Autodesk Fusion 360 part; units mm, degrees
(part 4 of 5)
extrude "flange screw hole (1)" cut sketch "flange screw hole" along normal blind 26 bodies 30 in component "Gripper handle (printed)"
ref_plane "WorkPlane17" through (12.3, 0, 0) normal (1, 0, 0) x (0, 1, 0) in component "Gripper handle (printed)"
sketch "flange screw tunnel" plane through (12.3, 0, 0) normal (1, 0, 0) x (0, 0, -1) in component "Gripper handle (printed)"
  circle A0 centre (-5, 9.5) radius 3.2
extrude "flange screw tunnel (1)" cut sketch "flange screw tunnel" along normal blind 131.7 bodies 30 in component "Gripper handle (printed)"
sketch "flange screw hole (1)" plane through (7.3, 0, 0) normal (1, 0, 0) x (0, 0, -1) in component "Gripper handle (printed)"
  circle A0 centre (-8, 16.5) radius 1.7
extrude "flange screw hole (2)" cut sketch "flange screw hole (1)" along normal blind 26 bodies 30 in component "Gripper handle (printed)"
sketch "flange screw tunnel (1)" plane through (12.3, 0, 0) normal (1, 0, 0) x (0, 0, -1) in component "Gripper handle (printed)"
  circle A0 centre (-8, 16.5) radius 3.2
extrude "flange screw tunnel (2)" cut sketch "flange screw tunnel (1)" along normal blind 131.7 bodies 30 in component "Gripper handle (printed)"
ref_plane "WorkPlane18" through (0, 13, 0) normal (0, 1, 0) x (0, 0, 1) in component "Gripper handle (printed)"
sketch "rail insert hole (3)" plane through (0, 13, 0) normal (0, 1, 0) x (1, 0, 0) in component "Gripper handle (printed)"
  circle A0 centre (22.5, 0) radius 2
extrude "rail insert hole (1)'" cut sketch "rail insert hole (3)" along normal blind 8 bodies 30 in component "Gripper handle (printed)"
sketch "rail insert hole (1) (2)" plane through (0, 13, 0) normal (0, 1, 0) x (1, 0, 0) in component "Gripper handle (printed)"
  circle A0 centre (72.5, 0) radius 2
extrude "rail insert hole (2)'" cut sketch "rail insert hole (1) (2)" along normal blind 8 bodies 30 in component "Gripper handle (printed)"
sketch "rail insert hole (2) (2)" plane through (0, 13, 0) normal (0, 1, 0) x (1, 0, 0) in component "Gripper handle (printed)"
  circle A0 centre (122.5, 0) radius 2
extrude "rail insert hole (3)'" cut sketch "rail insert hole (2) (2)" along normal blind 8 bodies 30 in component "Gripper handle (printed)"
ref_plane "WorkPlane19" through (0, 18, 0) normal (0, 1, 0) x (0, 0, 1) in component "Gripper handle (printed)"
sketch "pusher insert hole" plane through (0, 18, 0) normal (0, 1, 0) x (1, 0, 0) in component "Gripper handle (printed)"
  circle A0 centre (122.5, -58) radius 2
extrude "pusher insert hole (1)" cut sketch "pusher insert hole" along normal blind 7 bodies 30 in component "Gripper handle (printed)"
ref_plane "WorkPlane1" through (0, 15.9, 0) normal (0, 1, 0) x (0, 0, 1) in component "Gripper HW fixed (buy)"
sketch "#4 x 3/8\" pan-head self-tapping screw, pipe (buy)" plane through (0, 15.9, 0) normal (0, 1, 0) x (1, 0, 0) in component "Gripper HW fixed (buy)"
  circle A0 centre (-124, 0) radius 2.8
extrude "#4 x 3/8\" pan-head self-tapping screw, pipe (buy) (1)" add sketch "#4 x 3/8\" pan-head self-tapping screw, pipe (buy)" against normal blind 2.4 separate body makes body 41 in component "Gripper HW fixed (buy)"
ref_plane "WorkPlane2" through (0, 13.5, 0) normal (0, 1, 0) x (0, 0, 1) in component "Gripper HW fixed (buy)"
sketch "#4 x 3/8\" pan-head self-tapping screw, pipe (buy) shank" plane through (0, 13.5, 0) normal (0, 1, 0) x (1, 0, 0) in component "Gripper HW fixed (buy)"
  circle A0 centre (-124, 0) radius 1.45
extrude "#4 x 3/8\" pan-head self-tapping screw, pipe (buy) shank (1)" add sketch "#4 x 3/8\" pan-head self-tapping screw, pipe (buy) shank" against normal blind 9.5 bodies 41 in component "Gripper HW fixed (buy)"
sketch "#4 x 3/8\" pan-head self-tapping screw, pipe (buy) (1)" plane through (0, 15.9, 0) normal (0, 1, 0) x (1, 0, 0) in component "Gripper HW fixed (buy)"
  circle A0 centre (-44, 0) radius 2.8
extrude "#4 x 3/8\" pan-head self-tapping screw, pipe (buy) (2)" add sketch "#4 x 3/8\" pan-head self-tapping screw, pipe (buy) (1)" against normal blind 2.4 separate body makes body 42 in component "Gripper HW fixed (buy)"
sketch "#4 x 3/8\" pan-head self-tapping screw, pipe (buy) shank (1)" plane through (0, 13.5, 0) normal (0, 1, 0) x (1, 0, 0) in component "Gripper HW fixed (buy)"
  circle A0 centre (-44, 0) radius 1.45
extrude "#4 x 3/8\" pan-head self-tapping screw, pipe (buy) shank (2)" add sketch "#4 x 3/8\" pan-head self-tapping screw, pipe (buy) shank (1)" against normal blind 9.5 bodies 42 in component "Gripper HW fixed (buy)"
ref_plane "WorkPlane3" through (5.4, 0, 0) normal (1, 0, 0) x (0, 1, 0) in component "Gripper HW fixed (buy)"
sketch "#4 x 3/8\" pan-head self-tapping screw, ring (buy)" plane through (5.4, 0, 0) normal (1, 0, 0) x (0, 0, -1) in component "Gripper HW fixed (buy)"
  circle A0 centre (0, 13.5) radius 2.8
extrude "#4 x 3/8\" pan-head self-tapping screw, ring (buy) (1)" add sketch "#4 x 3/8\" pan-head self-tapping screw, ring (buy)" against normal blind 2.4 separate body makes body 43 in component "Gripper HW fixed (buy)"
ref_plane "WorkPlane4" through (3, 0, 0) normal (1, 0, 0) x (0, 1, 0) in component "Gripper HW fixed (buy)"
sketch "#4 x 3/8\" pan-head self-tapping screw, ring (buy) shank" plane through (3, 0, 0) normal (1, 0, 0) x (0, 0, -1) in component "Gripper HW fixed (buy)"
  circle A0 centre (0, 13.5) radius 1.45
extrude "#4 x 3/8\" pan-head self-tapping screw, ring (buy) shank (1)" add sketch "#4 x 3/8\" pan-head self-tapping screw, ring (buy) shank" against normal blind 9.5 bodies 43 in component "Gripper HW fixed (buy)"
ref_plane "WorkPlane5" through (0, 27.5, 0) normal (0, 1, 0) x (0, 0, 1) in component "Gripper HW fixed (buy)"
sketch "M3 x 8 socket head, rail (buy)" plane through (0, 27.5, 0) normal (0, 1, 0) x (1, 0, 0) in component "Gripper HW fixed (buy)"
  circle A0 centre (-152.5, 0) radius 2.75
extrude "M3 x 8 socket head, rail (buy) (1)" add sketch "M3 x 8 socket head, rail (buy)" against normal blind 3 separate body makes body 44 in component "Gripper HW fixed (buy)"
ref_plane "WorkPlane6" through (0, 24.5, 0) normal (0, 1, 0) x (0, 0, 1) in component "Gripper HW fixed (buy)"
sketch "M3 x 8 socket head, rail (buy) shank" plane through (0, 24.5, 0) normal (0, 1, 0) x (1, 0, 0) in component "Gripper HW fixed (buy)"
  circle A0 centre (-152.5, 0) radius 1.5
extrude "M3 x 8 socket head, rail (buy) shank (1)" add sketch "M3 x 8 socket head, rail (buy) shank" against normal blind 8 bodies 44 in component "Gripper HW fixed (buy)"
ref_plane "WorkPlane7" through (0, 14.3, 0) normal (0, 1, 0) x (0, 0, 1) in component "Gripper HW fixed (buy)"
sketch "insert" plane through (0, 14.3, 0) normal (0, 1, 0) x (1, 0, 0) in component "Gripper HW fixed (buy)"
  circle A0 centre (-152.5, 0) radius 2
extrude "insert (1)" add sketch "insert" along normal blind 5.7 separate body makes body 45 in component "Gripper HW fixed (buy)"
sketch "M3 x 8 socket head, rail (buy) (1)" plane through (0, 27.5, 0) normal (0, 1, 0) x (1, 0, 0) in component "Gripper HW fixed (buy)"
  circle A0 centre (-102.5, 0) radius 2.75
extrude "M3 x 8 socket head, rail (buy) (2)" add sketch "M3 x 8 socket head, rail (buy) (1)" against normal blind 3 separate body makes body 46 in component "Gripper HW fixed (buy)"
sketch "M3 x 8 socket head, rail (buy) shank (1)" plane through (0, 24.5, 0) normal (0, 1, 0) x (1, 0, 0) in component "Gripper HW fixed (buy)"
  circle A0 centre (-102.5, 0) radius 1.5
extrude "M3 x 8 socket head, rail (buy) shank (2)" add sketch "M3 x 8 socket head, rail (buy) shank (1)" against normal blind 8 bodies 46 in component "Gripper HW fixed (buy)"
sketch "insert (1)" plane through (0, 14.3, 0) normal (0, 1, 0) x (1, 0, 0) in component "Gripper HW fixed (buy)"
  circle A0 centre (-102.5, 0) radius 2
extrude "insert (2)" add sketch "insert (1)" along normal blind 5.7 separate body makes body 47 in component "Gripper HW fixed (buy)"
sketch "M3 x 8 socket head, rail (buy) (2)" plane through (0, 27.5, 0) normal (0, 1, 0) x (1, 0, 0) in component "Gripper HW fixed (buy)"
  circle A0 centre (-52.5, 0) radius 2.75
extrude "M3 x 8 socket head, rail (buy) (3)" add sketch "M3 x 8 socket head, rail (buy) (2)" against normal blind 3 separate body makes body 48 in component "Gripper HW fixed (buy)"
sketch "M3 x 8 socket head, rail (buy) shank (2)" plane through (0, 24.5, 0) normal (0, 1, 0) x (1, 0, 0) in component "Gripper HW fixed (buy)"
  circle A0 centre (-52.5, 0) radius 1.5
extrude "M3 x 8 socket head, rail (buy) shank (3)" add sketch "M3 x 8 socket head, rail (buy) shank (2)" against normal blind 8 bodies 48 in component "Gripper HW fixed (buy)"
sketch "insert (2)" plane through (0, 14.3, 0) normal (0, 1, 0) x (1, 0, 0) in component "Gripper HW fixed (buy)"
  circle A0 centre (-52.5, 0) radius 2
extrude "insert (3)" add sketch "insert (2)" along normal blind 5.7 separate body makes body 49 in component "Gripper HW fixed (buy)"
sketch "M3 x 8 socket head, rail (buy) (3)" plane through (0, 27.5, 0) normal (0, 1, 0) x (1, 0, 0) in component "Gripper HW fixed (buy)"
  circle A0 centre (22.5, 0) radius 2.75
extrude "M3 x 8 socket head, rail (buy) (4)" add sketch "M3 x 8 socket head, rail (buy) (3)" against normal blind 3 separate body makes body 50 in component "Gripper HW fixed (buy)"
sketch "M3 x 8 socket head, rail (buy) shank (3)" plane through (0, 24.5, 0) normal (0, 1, 0) x (1, 0, 0) in component "Gripper HW fixed (buy)"
  circle A0 centre (22.5, 0) radius 1.5
extrude "M3 x 8 socket head, rail (buy) shank (4)" add sketch "M3 x 8 socket head, rail (buy) shank (3)" against normal blind 8 bodies 50 in component "Gripper HW fixed (buy)"
sketch "insert (3)" plane through (0, 14.3, 0) normal (0, 1, 0) x (1, 0, 0) in component "Gripper HW fixed (buy)"
  circle A0 centre (22.5, 0) radius 2
extrude "insert (4)" add sketch "insert (3)" along normal blind 5.7 separate body makes body 51 in component "Gripper HW fixed (buy)"
sketch "M3 x 8 socket head, rail (buy) (4)" plane through (0, 27.5, 0) normal (0, 1, 0) x (1, 0, 0) in component "Gripper HW fixed (buy)"
  circle A0 centre (72.5, 0) radius 2.75
extrude "M3 x 8 socket head, rail (buy) (5)" add sketch "M3 x 8 socket head, rail (buy) (4)" against normal blind 3 separate body makes body 52 in component "Gripper HW fixed (buy)"
sketch "M3 x 8 socket head, rail (buy) shank (4)" plane through (0, 24.5, 0) normal (0, 1, 0) x (1, 0, 0) in component "Gripper HW fixed (buy)"
  circle A0 centre (72.5, 0) radius 1.5
extrude "M3 x 8 socket head, rail (buy) shank (5)" add sketch "M3 x 8 socket head, rail (buy) shank (4)" against normal blind 8 bodies 52 in component "Gripper HW fixed (buy)"
sketch "insert (4)" plane through (0, 14.3, 0) normal (0, 1, 0) x (1, 0, 0) in component "Gripper HW fixed (buy)"
  circle A0 centre (72.5, 0) radius 2
extrude "insert (5)" add sketch "insert (4)" along normal blind 5.7 separate body makes body 53 in component "Gripper HW fixed (buy)"
sketch "M3 x 8 socket head, rail (buy) (5)" plane through (0, 27.5, 0) normal (0, 1, 0) x (1, 0, 0) in component "Gripper HW fixed (buy)"
  circle A0 centre (122.5, 0) radius 2.75
extrude "M3 x 8 socket head, rail (buy) (6)" add sketch "M3 x 8 socket head, rail (buy) (5)" against normal blind 3 separate body makes body 54 in component "Gripper HW fixed (buy)"
sketch "M3 x 8 socket head, rail (buy) shank (5)" plane through (0, 24.5, 0) normal (0, 1, 0) x (1, 0, 0) in component "Gripper HW fixed (buy)"
  circle A0 centre (122.5, 0) radius 1.5
extrude "M3 x 8 socket head, rail (buy) shank (6)" add sketch "M3 x 8 socket head, rail (buy) shank (5)" against normal blind 8 bodies 54 in component "Gripper HW fixed (buy)"
sketch "insert (5)" plane through (0, 14.3, 0) normal (0, 1, 0) x (1, 0, 0) in component "Gripper HW fixed (buy)"
  circle A0 centre (122.5, 0) radius 2
extrude "insert (6)" add sketch "insert (5)" along normal blind 5.7 separate body makes body 55 in component "Gripper HW fixed (buy)"
ref_plane "WorkPlane8" through (0, 31.5, 0) normal (0, 1, 0) x (0, 0, 1) in component "Gripper HW fixed (buy)"
sketch "M3 x 8 socket head, spool (buy)" plane through (0, 31.5, 0) normal (0, 1, 0) x (1, 0, 0) in component "Gripper HW fixed (buy)"
  circle A0 centre (-164, -22) radius 2.75
extrude "M3 x 8 socket head, spool (buy) (1)" add sketch "M3 x 8 socket head, spool (buy)" against normal blind 3 separate body makes body 56 in component "Gripper HW fixed (buy)"
ref_plane "WorkPlane9" through (0, 28.5, 0) normal (0, 1, 0) x (0, 0, 1) in component "Gripper HW fixed (buy)"
sketch "M3 x 8 socket head, spool (buy) shank" plane through (0, 28.5, 0) normal (0, 1, 0) x (1, 0, 0) in component "Gripper HW fixed (buy)"
  circle A0 centre (-164, -22) radius 1.5
extrude "M3 x 8 socket head, spool (buy) shank (1)" add sketch "M3 x 8 socket head, spool (buy) shank" against normal blind 8 bodies 56 in component "Gripper HW fixed (buy)"
ref_plane "WorkPlane10" through (0, 22.8, 0) normal (0, 1, 0) x (0, 0, 1) in component "Gripper HW fixed (buy)"
sketch "insert (6)" plane through (0, 22.8, 0) normal (0, 1, 0) x (1, 0, 0) in component "Gripper HW fixed (buy)"
  circle A0 centre (-164, -22) radius 2
extrude "insert (7)" add sketch "insert (6)" along normal blind 5.7 separate body makes body 57 in component "Gripper HW fixed (buy)"
ref_plane "WorkPlane11" through (15.3, 0, 0) normal (1, 0, 0) x (0, 1, 0) in component "Gripper HW fixed (buy)"
sketch "M3 x 8 socket head, handle flange (buy)" plane through (15.3, 0, 0) normal (1, 0, 0) x (0, 0, -1) in component "Gripper HW fixed (buy)"
  circle A0 centre (-5, 9.5) radius 2.75
extrude "M3 x 8 socket head, handle flange (buy) (1)" add sketch "M3 x 8 socket head, handle flange (buy)" against normal blind 3 separate body makes body 58 in component "Gripper HW fixed (buy)"
ref_plane "WorkPlane12" through (12.3, 0, 0) normal (1, 0, 0) x (0, 1, 0) in component "Gripper HW fixed (buy)"
sketch "M3 x 8 socket head, handle flange (buy) shank" plane through (12.3, 0, 0) normal (1, 0, 0) x (0, 0, -1) in component "Gripper HW fixed (buy)"
  circle A0 centre (-5, 9.5) radius 1.5
extrude "M3 x 8 socket head, handle flange (buy) shank (1)" add sketch "M3 x 8 socket head, handle flange (buy) shank" against normal blind 8 bodies 58 in component "Gripper HW fixed (buy)"
ref_plane "WorkPlane13" through (2.6, 0, 0) normal (1, 0, 0) x (0, 1, 0) in component "Gripper HW fixed (buy)"
sketch "insert (7)" plane through (2.6, 0, 0) normal (1, 0, 0) x (0, 0, -1) in component "Gripper HW fixed (buy)"
  circle A0 centre (-5, 9.5) radius 2
extrude "insert (8)" add sketch "insert (7)" along normal blind 5.7 separate body makes body 59 in component "Gripper HW fixed (buy)"
sketch "M3 x 8 socket head, handle flange (buy) (1)" plane through (15.3, 0, 0) normal (1, 0, 0) x (0, 0, -1) in component "Gripper HW fixed (buy)"
  circle A0 centre (-8, 16.5) radius 2.75
extrude "M3 x 8 socket head, handle flange (buy) (2)" add sketch "M3 x 8 socket head, handle flange (buy) (1)" against normal blind 3 separate body makes body 60 in component "Gripper HW fixed (buy)"
sketch "M3 x 8 socket head, handle flange (buy) shank (1)" plane through (12.3, 0, 0) normal (1, 0, 0) x (0, 0, -1) in component "Gripper HW fixed (buy)"
  circle A0 centre (-8, 16.5) radius 1.5
extrude "M3 x 8 socket head, handle flange (buy) shank (2)" add sketch "M3 x 8 socket head, handle flange (buy) shank (1)" against normal blind 8 bodies 60 in component "Gripper HW fixed (buy)"
sketch "insert (8)" plane through (2.6, 0, 0) normal (1, 0, 0) x (0, 0, -1) in component "Gripper HW fixed (buy)"
  circle A0 centre (-8, 16.5) radius 2
extrude "insert (9)" add sketch "insert (8)" along normal blind 5.7 separate body makes body 61 in component "Gripper HW fixed (buy)"
ref_plane "WorkPlane1" through (0, 20.2, 0) normal (0, 1, 0) x (0, 0, 1) in component "Gripper spool (printed)"
sketch "hub (2)" plane through (0, 20.2, 0) normal (0, 1, 0) x (1, 0, 0) in component "Gripper spool (printed)"
  circle A0 centre (-164, -22) radius 5.2
  circle A1 centre (-164, -22) radius 4.2
extrude "hub (1)'" add sketch "hub (2)" along normal blind 7.8 separate body makes body 62 in component "Gripper spool (printed)"
ref_plane "WorkPlane2" through (0, 27.5, 0) normal (0, 1, 0) x (0, 0, 1) in component "Gripper spool (printed)"
sketch "flange" plane through (0, 27.5, 0) normal (0, 1, 0) x (1, 0, 0) in component "Gripper spool (printed)"
  circle A0 centre (-164, -22) radius 8
  circle A1 centre (-164, -22) radius 4.2
extrude "flange (1)" add sketch "flange" along normal blind 1 separate body makes body 63 in component "Gripper spool (printed)"
combine "Combine1'''''''" operation add target body 62 tool bodies 63 in component "Gripper spool (printed)"
ref_plane "WorkPlane14" through (0, 21, 0) normal (0, 1, 0) x (0, 0, 1) in component "Gripper HW fixed (buy)"
sketch "coil" plane through (0, 21, 0) normal (0, 1, 0) x (1, 0, 0) in component "Gripper HW fixed (buy)"
  circle A0 centre (-164, -22) radius 8
  circle A1 centre (-164, -22) radius 5.2
extrude "coil (1)" add sketch "coil" along normal blind 6 separate body makes body 64 in component "Gripper HW fixed (buy)"
ref_plane "WorkPlane15" through (0, 0, 14.1) normal (0, 0, 1) x (1, 0, 0) in component "Gripper HW fixed (buy)"
sketch "tape" plane through (0, 0, 14.1) normal (0, 0, 1) x (1, 0, 0) in component "Gripper HW fixed (buy)"
  line L0 (-164, 21) -> (-156, 21)
  line L1 (-156, 21) -> (-156, 27)
  line L2 (-156, 27) -> (-164, 27)
  line L3 (-164, 27) -> (-164, 21)
extrude "tape (1)" add sketch "tape" along normal blind 0.2 separate body makes body 65 in component "Gripper HW fixed (buy)"
ref_plane "WorkPlane16" through (0, 32, 0) normal (0, 1, 0) x (0, 0, 1) in component "Gripper HW fixed (buy)"
sketch "M3 x 10 socket head, pusher pivot (buy)" plane through (0, 32, 0) normal (0, 1, 0) x (1, 0, 0) in component "Gripper HW fixed (buy)"
  circle A0 centre (122.5, -58) radius 2.75
extrude "M3 x 10 socket head, pusher pivot (buy) (1)" add sketch "M3 x 10 socket head, pusher pivot (buy)" against normal blind 3 separate body makes body 66 in component "Gripper HW fixed (buy)"
ref_plane "WorkPlane17" through (0, 29, 0) normal (0, 1, 0) x (0, 0, 1) in component "Gripper HW fixed (buy)"
sketch "M3 x 10 socket head, pusher pivot (buy) shank" plane through (0, 29, 0) normal (0, 1, 0) x (1, 0, 0) in component "Gripper HW fixed (buy)"
  circle A0 centre (122.5, -58) radius 1.5
extrude "M3 x 10 socket head, pusher pivot (buy) shank (1)" add sketch "M3 x 10 socket head, pusher pivot (buy) shank" against normal blind 10 bodies 66 in component "Gripper HW fixed (buy)"
ref_plane "WorkPlane18" through (0, 18.3, 0) normal (0, 1, 0) x (0, 0, 1) in component "Gripper HW fixed (buy)"
sketch "insert (9)" plane through (0, 18.3, 0) normal (0, 1, 0) x (1, 0, 0) in component "Gripper HW fixed (buy)"
  circle A0 centre (122.5, -58) radius 2
extrude "insert (10)" add sketch "insert (9)" along normal blind 5.7 separate body makes body 67 in component "Gripper HW fixed (buy)"
ref_plane "WorkPlane19" through (0, 0, -39) normal (0, 0, 1) x (1, 0, 0) in component "Gripper HW fixed (buy)"
sketch "plunger" plane through (0, 0, -39) normal (0, 0, 1) x (1, 0, 0) in component "Gripper HW fixed (buy)"
  circle A0 centre (108, 36) radius 3.9
extrude "plunger (1)" add sketch "plunger" along normal blind 10 separate body makes body 68 in component "Gripper HW fixed (buy)"
ref_plane "WorkPlane20" through (0, 0, -29) normal (0, 0, 1) x (1, 0, 0) in component "Gripper HW fixed (buy)"
sketch "pin" plane through (0, 0, -29) normal (0, 0, 1) x (1, 0, 0) in component "Gripper HW fixed (buy)"
  circle A0 centre (108, 36) radius 2.5
extrude "pin (1)" add sketch "pin" along normal blind 8 separate body makes body 69 in component "Gripper HW fixed (buy)"
ref_plane "WorkPlane21" through (0, 0, -49) normal (0, 0, 1) x (1, 0, 0) in component "Gripper HW fixed (buy)"
sketch "knob" plane through (0, 0, -49) normal (0, 0, 1) x (1, 0, 0) in component "Gripper HW fixed (buy)"
  circle A0 centre (108, 36) radius 7
extrude "knob (1)" add sketch "knob" along normal blind 10 separate body makes body 70 in component "Gripper HW fixed (buy)"
combine "Combine1''''''''" operation add target body 68 tool bodies 69 in component "Gripper HW fixed (buy)"
combine "Combine2'''''" operation add target body 68 tool bodies 70 in component "Gripper HW fixed (buy)"
ref_plane "WorkPlane22" through (0, 0, -11.5) normal (0, 0, 1) x (1, 0, 0) in component "Gripper HW fixed (buy)"
sketch "M3 x 40 socket head, trigger pivot (buy)" plane through (0, 0, -11.5) normal (0, 0, 1) x (1, 0, 0) in component "Gripper HW fixed (buy)"
  circle A0 centre (100, -4) radius 2.75
extrude "M3 x 40 socket head, trigger pivot (buy) (1)" add sketch "M3 x 40 socket head, trigger pivot (buy)" along normal blind 3 separate body makes body 71 in component "Gripper HW fixed (buy)"
ref_plane "WorkPlane23" through (0, 0, -8.5) normal (0, 0, 1) x (1, 0, 0) in component "Gripper HW fixed (buy)"
sketch "M3 x 40 socket head, trigger pivot (buy) shank" plane through (0, 0, -8.5) normal (0, 0, 1) x (1, 0, 0) in component "Gripper HW fixed (buy)"
  circle A0 centre (100, -4) radius 1.5
extrude "M3 x 40 socket head, trigger pivot (buy) shank (1)" add sketch "M3 x 40 socket head, trigger pivot (buy) shank" along normal blind 40 bodies 71 in component "Gripper HW fixed (buy)"
sketch "paths" plane through (0, 0, 0) normal (0, 0, 1) x (1, 0, 0) in component "Gripper HW fixed (buy)"
  line L0 (89, 13.5, 16) -> (77, 13.5, 16)
  line L1 (77, 13.5, 16) -> (70.8197, 13.5, 16.9789)
  line L2 (70.8197, 13.5, 16.9789) -> (65.2443, 13.5, 19.8197)
  line L3 (65.2443, 13.5, 19.8197) -> (60.8197, 13.5, 24.2443)
  line L4 (60.8197, 13.5, 24.2443) -> (57.9789, 14.7737, 29.8197)
  line L5 (57.9789, 14.7737, 29.8197) -> (57, 17.5655, 36)
  line L6 (57, 17.5655, 36) -> (57.9789, 20.3573, 42.1803)
  line L7 (57.9789, 20.3573, 42.1803) -> (60.8197, 22.8759, 47.7557)
  line L8 (60.8197, 22.8759, 47.7557) -> (65.2443, 24.8746, 52.1803)
  line L9 (65.2443, 24.8746, 52.1803) -> (70.8197, 26.1578, 55.0211)
  line L10 (70.8197, 26.1578, 55.0211) -> (77, 26.6, 56)
  line L11 (77, 26.6, 56) -> (90.5, 26.6, 52.012)
  line L12 (90.5, 26.6, 52.012) -> (98.5, 26.6, 52.012)
  line L13 (108.2, 13.5, 16) -> (89, 13.5, 16)
  line L14 (89, 13.5, 16) -> (77, 13.5, 16)
  line L15 (77, 13.5, 16) -> (70.8197, 13.5, 16.9789)
  line L16 (70.8197, 13.5, 16.9789) -> (65.2443, 13.5, 19.8197)
  line L17 (65.2443, 13.5, 19.8197) -> (60.8197, 13.5, 24.2443)
  line L18 (60.8197, 13.5, 24.2443) -> (57.9789, 14.7737, 29.8197)
  line L19 (57.9789, 14.7737, 29.8197) -> (57, 17.5655, 36)
  line L20 (57, 17.5655, 36) -> (57.9789, 20.3573, 42.1803)
  line L21 (57.9789, 20.3573, 42.1803) -> (60.8197, 22.8759, 47.7557)
  line L22 (60.8197, 22.8759, 47.7557) -> (65.2443, 24.8746, 52.1803)
  line L23 (65.2443, 24.8746, 52.1803) -> (70.8197, 26.1578, 55.0211)
  line L24 (70.8197, 26.1578, 55.0211) -> (77, 26.6, 56)
  line L25 (77, 26.6, 56) -> (90.5, 26.6, 52.012)
  line L26 (90.5, 26.6, 52.012) -> (98.5, 26.6, 52.012)
  line L27 (98.5, 26.6, 52.012) -> (104.5, 26.6, 52.012)
  line L28 (104.5, 26.6, 52.012) -> (122.1203, 26.6, 52.012)
  line L29 (122.1203, 26.6, 52.012) -> (130.8203, 26.6, 52.012)
pipe "cable housing" add diameter 5 path "paths" along L0 separate body makes body 72 in component "Gripper HW fixed (buy)"
pipe "cable housing (1)" add diameter 5 path "paths" along L1 separate body makes body 73 in component "Gripper HW fixed (buy)"
pipe "cable housing (2)" add diameter 5 path "paths" along L2 separate body makes body 74 in component "Gripper HW fixed (buy)"
pipe "cable housing (3)" add diameter 5 path "paths" along L3 separate body makes body 75 in component "Gripper HW fixed (buy)"
pipe "cable housing (4)" add diameter 5 path "paths" along L4 separate body makes body 76 in component "Gripper HW fixed (buy)"
pipe "cable housing (5)" add diameter 5 path "paths" along L5 separate body makes body 77 in component "Gripper HW fixed (buy)"
pipe "cable housing (6)" add diameter 5 path "paths" along L6 separate body makes body 78 in component "Gripper HW fixed (buy)"
pipe "cable housing (7)" add diameter 5 path "paths" along L7 separate body makes body 79 in component "Gripper HW fixed (buy)"
pipe "cable housing (8)" add diameter 5 path "paths" along L8 separate body makes body 80 in component "Gripper HW fixed (buy)"
pipe "cable housing (9)" add diameter 5 path "paths" along L9 separate body makes body 81 in component "Gripper HW fixed (buy)"
pipe "cable housing (10)" add diameter 5 path "paths" along L10 separate body makes body 82 in component "Gripper HW fixed (buy)"
pipe "cable housing (11)" add diameter 5 path "paths" along L11 separate body makes body 83 in component "Gripper HW fixed (buy)"
pipe "cable housing (12)" add diameter 5 path "paths" along L12 separate body makes body 84 in component "Gripper HW fixed (buy)"
combine "Combine3'''" operation add target body 72 tool bodies 73 in component "Gripper HW fixed (buy)"
combine "Combine4'''" operation add target body 72 tool bodies 74 in component "Gripper HW fixed (buy)"
combine "Combine5'''" operation add target body 72 tool bodies 75 in component "Gripper HW fixed (buy)"
combine "Combine6''" operation add target body 72 tool bodies 76 in component "Gripper HW fixed (buy)"
combine "Combine7''" operation add target body 72 tool bodies 77 in component "Gripper HW fixed (buy)"
combine "Combine8'" operation add target body 72 tool bodies 78 in component "Gripper HW fixed (buy)"
combine "Combine9'" operation add target body 72 tool bodies 79 in component "Gripper HW fixed (buy)"
combine "Combine10'" operation add target body 72 tool bodies 80 in component "Gripper HW fixed (buy)"
combine "Combine11" operation add target body 72 tool bodies 81 in component "Gripper HW fixed (buy)"
combine "Combine12" operation add target body 72 tool bodies 82 in component "Gripper HW fixed (buy)"
combine "Combine13" operation add target body 72 tool bodies 83 in component "Gripper HW fixed (buy)"
combine "Combine14" operation add target body 72 tool bodies 84 in component "Gripper HW fixed (buy)"
pipe "inner wire" add diameter 1.5 path "paths" along L13 separate body makes body 85 in component "Gripper HW fixed (buy)"
pipe "inner wire (1)" add diameter 1.5 path "paths" along L14 separate body makes body 86 in component "Gripper HW fixed (buy)"
pipe "inner wire (2)" add diameter 1.5 path "paths" along L15 separate body makes body 87 in component "Gripper HW fixed (buy)"
pipe "inner wire (3)" add diameter 1.5 path "paths" along L16 separate body makes body 88 in component "Gripper HW fixed (buy)"
pipe "inner wire (4)" add diameter 1.5 path "paths" along L17 separate body makes body 89 in component "Gripper HW fixed (buy)"
pipe "inner wire (5)" add diameter 1.5 path "paths" along L18 separate body makes body 90 in component "Gripper HW fixed (buy)"
pipe "inner wire (6)" add diameter 1.5 path "paths" along L19 separate body makes body 91 in component "Gripper HW fixed (buy)"
pipe "inner wire (7)" add diameter 1.5 path "paths" along L20 separate body makes body 92 in component "Gripper HW fixed (buy)"
pipe "inner wire (8)" add diameter 1.5 path "paths" along L21 separate body makes body 93 in component "Gripper HW fixed (buy)"
pipe "inner wire (9)" add diameter 1.5 path "paths" along L22 separate body makes body 94 in component "Gripper HW fixed (buy)"
pipe "inner wire (10)" add diameter 1.5 path "paths" along L23 separate body makes body 95 in component "Gripper HW fixed (buy)"
pipe "inner wire (11)" add diameter 1.5 path "paths" along L24 separate body makes body 96 in component "Gripper HW fixed (buy)"
pipe "inner wire (12)" add diameter 1.5 path "paths" along L25 separate body makes body 97 in component "Gripper HW fixed (buy)"
pipe "inner wire (13)" add diameter 1.5 path "paths" along L26 separate body makes body 98 in component "Gripper HW fixed (buy)"
pipe "inner wire (14)" add diameter 1.5 path "paths" along L27 separate body makes body 99 in component "Gripper HW fixed (buy)"
pipe "inner wire (15)" add diameter 1.5 path "paths" along L28 separate body makes body 100 in component "Gripper HW fixed (buy)"
pipe "inner wire (16)" add diameter 1.5 path "paths" along L29 separate body makes body 101 in component "Gripper HW fixed (buy)"
combine "Combine15" operation add target body 85 tool bodies 86 in component "Gripper HW fixed (buy)"
combine "Combine16" operation add target body 85 tool bodies 87 in component "Gripper HW fixed (buy)"
combine "Combine17" operation add target body 85 tool bodies 88 in component "Gripper HW fixed (buy)"
combine "Combine18" operation add target body 85 tool bodies 89 in component "Gripper HW fixed (buy)"
combine "Combine19" operation add target body 85 tool bodies 90 in component "Gripper HW fixed (buy)"
combine "Combine20" operation add target body 85 tool bodies 91 in component "Gripper HW fixed (buy)"
combine "Combine21" operation add target body 85 tool bodies 92 in component "Gripper HW fixed (buy)"
combine "Combine22" operation add target body 85 tool bodies 93 in component "Gripper HW fixed (buy)"
combine "Combine23" operation add target body 85 tool bodies 94 in component "Gripper HW fixed (buy)"
combine "Combine24" operation add target body 85 tool bodies 95 in component "Gripper HW fixed (buy)"
combine "Combine25" operation add target body 85 tool bodies 96 in component "Gripper HW fixed (buy)"
combine "Combine26" operation add target body 85 tool bodies 97 in component "Gripper HW fixed (buy)"
combine "Combine27" operation add target body 85 tool bodies 98 in component "Gripper HW fixed (buy)"
combine "Combine28" operation add target body 85 tool bodies 99 in component "Gripper HW fixed (buy)"
combine "Combine29" operation add target body 85 tool bodies 100 in component "Gripper HW fixed (buy)"
combine "Combine30" operation add target body 85 tool bodies 101 in component "Gripper HW fixed (buy)"
ref_plane "WorkPlane1" through (105.2, 0, 0) normal (1, 0, 0) x (0, 1, 0) in component "Gripper HW trigger nipple (buy)"
sketch "cylinder" plane through (105.2, 0, 0) normal (1, 0, 0) x (0, 0, -1) in component "Gripper HW trigger nipple (buy)"
  circle A0 centre (-16, 13.5) radius 3
extrude "cylinder (1)" add sketch "cylinder" along normal blind 6 separate body makes body 102 in component "Gripper HW trigger nipple (buy)"
ref_plane "WorkPlane1" through (126.8203, 0, 0) normal (1, 0, 0) x (0, 1, 0) in component "Gripper HW pusher nipple (buy)"
sketch "cylinder (2)" plane through (126.8203, 0, 0) normal (1, 0, 0) x (0, 0, -1) in component "Gripper HW pusher nipple (buy)"
  circle A0 centre (-52.012, 26.6) radius 3.25
extrude "cylinder (1)'" add sketch "cylinder (2)" along normal blind 8 separate body makes body 103 in component "Gripper HW pusher nipple (buy)"
ref_plane "WorkPlane1" through (0, 52.8, 0) normal (0, 1, 0) x (0, 0, 1) in component "Gripper HW head (buy)"
sketch "M3 x 16 socket head, gear axle (buy)" plane through (0, 52.8, 0) normal (0, 1, 0) x (1, 0, 0) in component "Gripper HW head (buy)"
  circle A0 centre (-136, -9.5) radius 2.75
extrude "M3 x 16 socket head, gear axle (buy) (1)" add sketch "M3 x 16 socket head, gear axle (buy)" against normal blind 3 separate body makes body 104 in component "Gripper HW head (buy)"
ref_plane "WorkPlane2" through (0, 49.8, 0) normal (0, 1, 0) x (0, 0, 1) in component "Gripper HW head (buy)"
sketch "M3 x 16 socket head, gear axle (buy) shank" plane through (0, 49.8, 0) normal (0, 1, 0) x (1, 0, 0) in component "Gripper HW head (buy)"
  circle A0 centre (-136, -9.5) radius 1.5
extrude "M3 x 16 socket head, gear axle (buy) shank (1)" add sketch "M3 x 16 socket head, gear axle (buy) shank" against normal blind 16 bodies 104 in component "Gripper HW head (buy)"
ref_plane "WorkPlane3" through (0, 33.3, 0) normal (0, 1, 0) x (0, 0, 1) in component "Gripper HW head (buy)"
sketch "insert (10)" plane through (0, 33.3, 0) normal (0, 1, 0) x (1, 0, 0) in component "Gripper HW head (buy)"
  circle A0 centre (-136, -9.5) radius 2
extrude "insert (1)'" add sketch "insert (10)" along normal blind 5.7 separate body makes body 105 in component "Gripper HW head (buy)"
sketch "M3 x 16 socket head, gear axle (buy) (1)" plane through (0, 52.8, 0) normal (0, 1, 0) x (1, 0, 0) in component "Gripper HW head (buy)"
  circle A0 centre (-136, 9.5) radius 2.75
extrude "M3 x 16 socket head, gear axle (buy) (2)" add sketch "M3 x 16 socket head, gear axle (buy) (1)" against normal blind 3 separate body makes body 106 in component "Gripper HW head (buy)"
sketch "M3 x 16 socket head, gear axle (buy) shank (1)" plane through (0, 49.8, 0) normal (0, 1, 0) x (1, 0, 0) in component "Gripper HW head (buy)"
  circle A0 centre (-136, 9.5) radius 1.5
extrude "M3 x 16 socket head, gear axle (buy) shank (2)" add sketch "M3 x 16 socket head, gear axle (buy) shank (1)" against normal blind 16 bodies 106 in component "Gripper HW head (buy)"
sketch "insert (1) (2)" plane through (0, 33.3, 0) normal (0, 1, 0) x (1, 0, 0) in component "Gripper HW head (buy)"
  circle A0 centre (-136, 9.5) radius 2
extrude "insert (2)'" add sketch "insert (1) (2)" along normal blind 5.7 separate body makes body 107 in component "Gripper HW head (buy)"
sketch "M3 x 8 socket head, lid (buy)" plane through (0, 52.8, 0) normal (0, 1, 0) x (1, 0, 0) in component "Gripper HW head (buy)"
  circle A0 centre (-151.5, -19) radius 2.75
extrude "M3 x 8 socket head, lid (buy) (1)" add sketch "M3 x 8 socket head, lid (buy)" against normal blind 3 separate body makes body 108 in component "Gripper HW head (buy)"
sketch "M3 x 8 socket head, lid (buy) shank" plane through (0, 49.8, 0) normal (0, 1, 0) x (1, 0, 0) in component "Gripper HW head (buy)"
  circle A0 centre (-151.5, -19) radius 1.5
extrude "M3 x 8 socket head, lid (buy) shank (1)" add sketch "M3 x 8 socket head, lid (buy) shank" against normal blind 8 bodies 108 in component "Gripper HW head (buy)"
ref_plane "WorkPlane4" through (0, 40.1, 0) normal (0, 1, 0) x (0, 0, 1) in component "Gripper HW head (buy)"
sketch "insert (2) (2)" plane through (0, 40.1, 0) normal (0, 1, 0) x (1, 0, 0) in component "Gripper HW head (buy)"
  circle A0 centre (-151.5, -19) radius 2
extrude "insert (3)'" add sketch "insert (2) (2)" along normal blind 5.7 separate body makes body 109 in component "Gripper HW head (buy)"
sketch "M3 x 8 socket head, lid (buy) (1)" plane through (0, 52.8, 0) normal (0, 1, 0) x (1, 0, 0) in component "Gripper HW head (buy)"
  circle A0 centre (-151.5, 19) radius 2.75
extrude "M3 x 8 socket head, lid (buy) (2)" add sketch "M3 x 8 socket head, lid (buy) (1)" against normal blind 3 separate body makes body 110 in component "Gripper HW head (buy)"
sketch "M3 x 8 socket head, lid (buy) shank (1)" plane through (0, 49.8, 0) normal (0, 1, 0) x (1, 0, 0) in component "Gripper HW head (buy)"
  circle A0 centre (-151.5, 19) radius 1.5
extrude "M3 x 8 socket head, lid (buy) shank (2)" add sketch "M3 x 8 socket head, lid (buy) shank (1)" against normal blind 8 bodies 110 in component "Gripper HW head (buy)"
sketch "insert (3) (2)" plane through (0, 40.1, 0) normal (0, 1, 0) x (1, 0, 0) in component "Gripper HW head (buy)"
  circle A0 centre (-151.5, 19) radius 2
extrude "insert (4)'" add sketch "insert (3) (2)" along normal blind 5.7 separate body makes body 111 in component "Gripper HW head (buy)"
ref_plane "WorkPlane5" through (0, 38.8, 0) normal (0, 1, 0) x (0, 0, 1) in component "Gripper HW head (buy)"
sketch "M3 x 8 socket head, carriage (buy)" plane through (0, 38.8, 0) normal (0, 1, 0) x (1, 0, 0) in component "Gripper HW head (buy)"
  circle A0 centre (-149, 10) radius 2.75
extrude "M3 x 8 socket head, carriage (buy) (1)" add sketch "M3 x 8 socket head, carriage (buy)" against normal blind 3 separate body makes body 112 in component "Gripper HW head (buy)"
ref_plane "WorkPlane6" through (0, 35.8, 0) normal (0, 1, 0) x (0, 0, 1) in component "Gripper HW head (buy)"
sketch "M3 x 8 socket head, carriage (buy) shank" plane through (0, 35.8, 0) normal (0, 1, 0) x (1, 0, 0) in component "Gripper HW head (buy)"
  circle A0 centre (-149, 10) radius 1.5
extrude "M3 x 8 socket head, carriage (buy) shank (1)" add sketch "M3 x 8 socket head, carriage (buy) shank" against normal blind 8 bodies 112 in component "Gripper HW head (buy)"
sketch "M3 x 8 socket head, carriage (buy) (1)" plane through (0, 38.8, 0) normal (0, 1, 0) x (1, 0, 0) in component "Gripper HW head (buy)"
  circle A0 centre (-149, -10) radius 2.75
extrude "M3 x 8 socket head, carriage (buy) (2)" add sketch "M3 x 8 socket head, carriage (buy) (1)" against normal blind 3 separate body makes body 113 in component "Gripper HW head (buy)"
sketch "M3 x 8 socket head, carriage (buy) shank (1)" plane through (0, 35.8, 0) normal (0, 1, 0) x (1, 0, 0) in component "Gripper HW head (buy)"
  circle A0 centre (-149, -10) radius 1.5
extrude "M3 x 8 socket head, carriage (buy) shank (2)" add sketch "M3 x 8 socket head, carriage (buy) shank (1)" against normal blind 8 bodies 113 in component "Gripper HW head (buy)"
sketch "M3 x 8 socket head, carriage (buy) (2)" plane through (0, 38.8, 0) normal (0, 1, 0) x (1, 0, 0) in component "Gripper HW head (buy)"
  circle A0 centre (-129, 10) radius 2.75
extrude "M3 x 8 socket head, carriage (buy) (3)" add sketch "M3 x 8 socket head, carriage (buy) (2)" against normal blind 3 separate body makes body 114 in component "Gripper HW head (buy)"
sketch "M3 x 8 socket head, carriage (buy) shank (2)" plane through (0, 35.8, 0) normal (0, 1, 0) x (1, 0, 0) in component "Gripper HW head (buy)"
  circle A0 centre (-129, 10) radius 1.5
extrude "M3 x 8 socket head, carriage (buy) shank (3)" add sketch "M3 x 8 socket head, carriage (buy) shank (2)" against normal blind 8 bodies 114 in component "Gripper HW head (buy)"
sketch "M3 x 8 socket head, carriage (buy) (3)" plane through (0, 38.8, 0) normal (0, 1, 0) x (1, 0, 0) in component "Gripper HW head (buy)"
  circle A0 centre (-129, -10) radius 2.75
extrude "M3 x 8 socket head, carriage (buy) (4)" add sketch "M3 x 8 socket head, carriage (buy) (3)" against normal blind 3 separate body makes body 115 in component "Gripper HW head (buy)"
sketch "M3 x 8 socket head, carriage (buy) shank (3)" plane through (0, 35.8, 0) normal (0, 1, 0) x (1, 0, 0) in component "Gripper HW head (buy)"
  circle A0 centre (-129, -10) radius 1.5
extrude "M3 x 8 socket head, carriage (buy) shank (4)" add sketch "M3 x 8 socket head, carriage (buy) shank (3)" against normal blind 8 bodies 115 in component "Gripper HW head (buy)"
ref_plane "WorkPlane1" through (0, 62.2, 0) normal (0, 1, 0) x (0, 0, 1) in component "Gripper HW finger R (buy)"
sketch "M3 x 16 socket head, finger (buy)" plane through (0, 62.2, 0) normal (0, 1, 0) x (1, 0, 0) in component "Gripper HW finger R (buy)"
  circle A0 centre (-114, -9.5) radius 2.75
extrude "M3 x 16 socket head, finger (buy) (1)" add sketch "M3 x 16 socket head, finger (buy)" against normal blind 3 separate body makes body 116 in component "Gripper HW finger R (buy)"
ref_plane "WorkPlane2" through (0, 59.2, 0) normal (0, 1, 0) x (0, 0, 1) in component "Gripper HW finger R (buy)"
sketch "M3 x 16 socket head, finger (buy) shank" plane through (0, 59.2, 0) normal (0, 1, 0) x (1, 0, 0) in component "Gripper HW finger R (buy)"
  circle A0 centre (-114, -9.5) radius 1.5
extrude "M3 x 16 socket head, finger (buy) shank (1)" add sketch "M3 x 16 socket head, finger (buy) shank" against normal blind 16 bodies 116 in component "Gripper HW finger R (buy)"
ref_plane "WorkPlane3" through (0, 39.7, 0) normal (0, 1, 0) x (0, 0, 1) in component "Gripper HW finger R (buy)"
sketch "insert (11)" plane through (0, 39.7, 0) normal (0, 1, 0) x (1, 0, 0) in component "Gripper HW finger R (buy)"
  circle A0 centre (-114, -9.5) radius 2
extrude "insert (1)''" add sketch "insert (11)" along normal blind 5.7 separate body makes body 117 in component "Gripper HW finger R (buy)"
ref_plane "WorkPlane1" through (0, 62.2, 0) normal (0, 1, 0) x (0, 0, 1) in component "Gripper HW finger L (buy)"
sketch "M3 x 16 socket head, finger (buy) (2)" plane through (0, 62.2, 0) normal (0, 1, 0) x (1, 0, 0) in component "Gripper HW finger L (buy)"
  circle A0 centre (-114, 9.5) radius 2.75
extrude "M3 x 16 socket head, finger (buy) (1)'" add sketch "M3 x 16 socket head, finger (buy) (2)" against normal blind 3 separate body makes body 118 in component "Gripper HW finger L (buy)"
ref_plane "WorkPlane2" through (0, 59.2, 0) normal (0, 1, 0) x (0, 0, 1) in component "Gripper HW finger L (buy)"
sketch "M3 x 16 socket head, finger (buy) shank (2)" plane through (0, 59.2, 0) normal (0, 1, 0) x (1, 0, 0) in component "Gripper HW finger L (buy)"
  circle A0 centre (-114, 9.5) radius 1.5
extrude "M3 x 16 socket head, finger (buy) shank (1)'" add sketch "M3 x 16 socket head, finger (buy) shank (2)" against normal blind 16 bodies 118 in component "Gripper HW finger L (buy)"
ref_plane "WorkPlane3" through (0, 39.7, 0) normal (0, 1, 0) x (0, 0, 1) in component "Gripper HW finger L (buy)"
sketch "insert (12)" plane through (0, 39.7, 0) normal (0, 1, 0) x (1, 0, 0) in component "Gripper HW finger L (buy)"
  circle A0 centre (-114, 9.5) radius 2
extrude "insert (1)'''" add sketch "insert (12)" along normal blind 5.7 separate body makes body 119 in component "Gripper HW finger L (buy)"
ref_plane "WorkPlane1" through (0, 16.8, 0) normal (0, 1, 0) x (0, 0, 1) in component "Gripper damper gear (buy)"